mdf-linkage (Autodesk Fusion 360 design; units mm, degrees)
Autodesk Fusion 360 part; units mm, degrees
sketch "스케치1" plane through (0, 0, 0) normal (0, 0, 1) x (1, 0, 0)
  line L0 (0, 0) -> (40, 0)
  line L1 (40, 0) -> (40, 20)
  line L2 (40, 20) -> (0, 20)
  line L3 (0, 20) -> (0, 0)
  circle A0 centre (35, 10) radius 2
  circle A1 centre (5, 5) radius 2
  circle A2 centre (15, 5) radius 2
  circle A3 centre (5, 15) radius 2
  circle A4 centre (15, 10) radius 2
  dimension "d1" = 40
  dimension "d2" = 20
  dimension "d3" = 4
  dimension "d4" = 4
  dimension "d5" = 4
  dimension "d6" = 4
  dimension "d7" = 4
  dimension "d8" = 5
  dimension "d9" = 15
  constraint horizontal L0
  constraint vertical L1
  constraint horizontal L2
  constraint vertical L3
  constraint coincident L0.start L3.end
  measures "d1" distance of L0.start L0.end
  measures "d2" distance of L0.start L2.end
  measures "d3" diameter of A0
  measures "d4" diameter of A1
  measures "d5" diameter of A2
  measures "d6" diameter of A3
  measures "d7" diameter of A4
  measures "d8" distance of L3 A3.centre
  measures "d9" distance of L0 A3.centre
extrude "돌출1" add sketch "스케치1" along normal blind 4.5 contours L0 L1 L2 L3 | A2 | A4 in component "Component"
sketch "스케치2" plane through (0, 0, 4.5) normal (0, 0, 1) x (-1, 0, 0)
  circle A0 centre (-5, -15) radius 2
  circle A1 centre (-35, -10) radius 2
  circle A2 centre (-5, -5) radius 2
  line L0 (0, -20) -> (0, 0)
  line L1 (0, 0) -> (-40, 0)
  line L2 (-40, 0) -> (-40, -20)
  line L3 (-40, -20) -> (0, -20)
  line L4 (-40, -20) -> (-30, -20)
  line L5 (-30, -20) -> (-30, 0)
  line L6 (-30, 0) -> (-40, 0)
  line L7 (-40, 0) -> (-40, -20)
  circle A3 centre (-15, -10) radius 2
  line L8 (-30, -20) -> (-20, -20)
  line L9 (-20, -20) -> (-20, 0)
  line L10 (-20, 0) -> (-30, 0)
  line L11 (-30, 0) -> (-30, -20)
  circle A4 centre (-15, -15) radius 5
  circle A5 centre (-15, -5) radius 5
  dimension "d12" = 4
  dimension "d13" = 10
  dimension "d14" = 5
  dimension "d15" = 5
  dimension "d16" = 10
  constraint horizontal L4
  constraint vertical L5
  constraint horizontal L6
  constraint vertical L7
  constraint coincident L1 L5.end
  constraint coincident L2.end L3.start
  constraint horizontal L8
  constraint vertical L9
  constraint horizontal L10
  constraint vertical L11
  constraint midpoint L1 L9.end
  measures "d12" diameter of A3
  measures "d13" diameter of A4
  measures "d14" distance of L9 A4.centre
  measures "d15" distance of L3 A4.centre
  measures "d16" diameter of A5
extrude "돌출2" cut sketch "스케치2" against normal blind 5 contours A3 A4 | A3 A4 A5 | A3 A4 A5 | A3 A5 picked at (-15.3661, -10.6661) picked at (-15.3661, -9.3339) in component "Component"
extrude "돌출3" cut sketch "스케치2" against normal blind 5 contours L3 L9 A4 | L1 L9 A5 | L1 L3 L5 L8 L9 L10 L11 | L1 L2 L3 L4 L5 L6 L7 L11 in component "Component"
pattern_linear "00000000-0000-0000-0000-000000000000" [suppressed]
component "Component" placed x (1, 0, 0) y (0, 1, 0) z (0, 0, 1) at (0, 0, 0)
component "Component" placed x (1, 0, 0) y (0, 1, 0) z (0, 0, 1) at (0, 20, 0)
component "Component" placed x (1, 0, 0) y (0, 1, 0) z (0, 0, 1) at (0, 40, 0)
component "Component" placed x (1, 0, 0) y (0, 1, 0) z (0, 0, 1) at (0, 60, 0)
component "Component" placed x (1, 0, 0) y (0, 1, 0) z (0, 0, 1) at (0, 80, 0)
component "Component" placed x (1, 0, 0) y (0, 1, 0) z (0, 0, 1) at (0, 100, 0)
component "Component" placed x (1, 0, 0) y (0, 1, 0) z (0, 0, 1) at (0, 120, 0)
component "Component" placed x (1, 0, 0) y (0, 1, 0) z (0, 0, 1) at (0, 140, 0)
